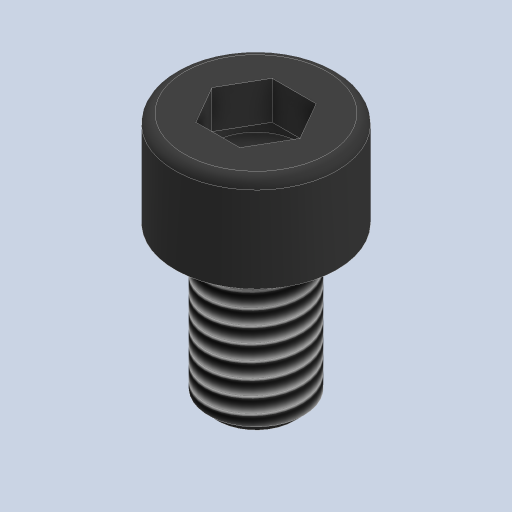
# Autodesk Inventor part: Parafuso allen cabeça cilíndrica DIN 912 M5x8
Saved by Autodesk Inventor 2024.3 (Build 283343000, 343)
## iProperties
Created: 2025-02-01
Part Number: Parafuso allen cabeça cilíndrica DIN 912 M5x8
Material: Aço, carbono
Document SubType Name: Modeling
Designer: Cliente
Density: 7.85 g/cm^3
Appearance: Aço - Polido
Mass: 3.09429 g
Surface Area: 4.0393 cm^2
Volume: 0.394177 cm^3
Author: Cliente
Autodesk Inventor part; units mm, degrees
ref_plane "YZ Plane" through (0, 0, 0) normal (1, 0, 0) x (0, 1, 0)
ref_plane "XZ Plane" through (0, 0, 0) normal (0, 1, 0) x (-1, 0, 0)
ref_plane "XY Plane" through (0, 0, 0) normal (0, 0, 1) x (1, 0, 0)
sketch "Esboço1" plane through (0, 0, 0) normal (0, 0, 1) x (1, 0, 0)
  line L0 (0, 0) -> (2.5, 0)
  line L1 (2.5, -0.2) -> (2.5, -7.5)
  line L2 (2.7, 0) -> (4.25, 0)
  line L3 (4.25, 0) -> (4.25, 4.5)
  line L4 (3.75, 5) -> (2.3094, 5)
  line L5 (2.3094, 5) -> (2.3094, 2.5)
  line L6 (2.3094, 2.5) -> (0, 1.1667)
  line L7 (2.3094, 2.5) -> (4.9761, 2.5) construction
  line L8 (2, -8) -> (0, -8)
  line L9 (0, -8) -> (0, 1.1667)
  arc A0 (4.25, 4.5) -> (3.75, 5) centre (3.75, 4.5) ccw
  arc A1 (2.7, 0) -> (2.5, -0.2) centre (2.7, -0.2) ccw
  line L10 (0, 12.1721) -> (2, 11.0174)
  line L11 (2, 11.0174) -> (2, 8.708)
  line L12 (2, 8.708) -> (0, 7.5533)
  line L13 (0, 7.5533) -> (-2, 8.708)
  line L14 (-2, 8.708) -> (-2, 11.0174)
  line L15 (-2, 11.0174) -> (0, 12.1721)
  line L16 (2.5, -7.5) -> (2, -8)
  point P0 (2.5, -8)
  point P1 (4.25, 5)
  point P2 (2, 0)
  point P3 (0, 9.8627)
  dimension "d0" = 2.5
  dimension "d1" = 8
  dimension "d2" = 4.25
  dimension "d3" = 5
  dimension "d5" = 2.5
  dimension "d6" = 150
  dimension "d8" = 0.5
  dimension "d9" = 0.2
  dimension "d10" = 4
  dimension "d11" = 4.6188
  dimension "d12" = 4.6188
  dimension "d17" = 0.5
  dimension "d18" = 0.5
  constraints: 34 end point, 6 point on line, 5 horizontal, 4 perpendicular, 4 point on circle, 4 tangent, 2 centre point, 2 vertical alignment, 1 equal length, 13 other
  measures "d0" distance of L0.start L0.end
  measures "d1" distance of L0.end point (2.5, -8)
  measures "d2" distance of L0.start L2.end
  measures "d3" distance of L2.end point (4.25, 5)
  measures "d5" distance of L4.end L5.end
  measures "d6" angle of L6 L7
  measures "d8" radius of A0
  measures "d9" radius of A1
  measures "d10" distance between parallel lines of L14 L11
  measures "d11" distance of L12.end L10.start
  measures "d12" diameter of L5 L9
  measures "d17" distance of L1.end point (2.5, -8)
  measures "d18" distance of L8.start point (2.5, -8)
revolve "Revolução1" add sketch "Esboço1" angle 360 about axis through (0, -8, 0) along (0, 1, 0) contours L1 L16 L8 L9 L6 L5 L4 A0 L3 L2 A1
sketch "Esboço2" plane through (0, 5, 0) normal (0, 1, 0) x (1, 0, 0)
  circle A0 centre (0, 0) radius 2.3094 projected
  circle A1 centre (0, 0) radius 3.75 projected
  line L0 (-2.3094, 0) -> (-1.1547, 2)
  line L1 (-1.1547, 2) -> (1.1547, 2)
  line L2 (1.1547, 2) -> (2.3094, 0)
  line L3 (2.3094, 0) -> (1.1547, -2)
  line L4 (1.1547, -2) -> (-1.1547, -2)
  line L5 (-1.1547, -2) -> (-2.3094, 0)
  point P0 (0, 0)
  point P1 (-1.1547, -2)
  point P2 (1.1547, -2)
  point P3 (2.3094, 0)
  point P4 (2.3094, 0)
  point P5 (1.1547, 2)
  point P6 (1.1547, 2)
  point P7 (-1.1547, 2)
  point P8 (-1.1547, 2)
  constraints: 12 end point, 1 coincident, 1 horizontal alignment, 15 other
extrude "Extrusão1" add sketch "Esboço2" against normal blind 2 contours L2 A0 | A0 L3 | L1 A0 | A0 L4 | L0 A0 | A0 L5
thread "Rosca1" size "M5x0.8" class "6g" standard "ANSI Metric M Profile" full length
equation "\"d18\" = d17"
